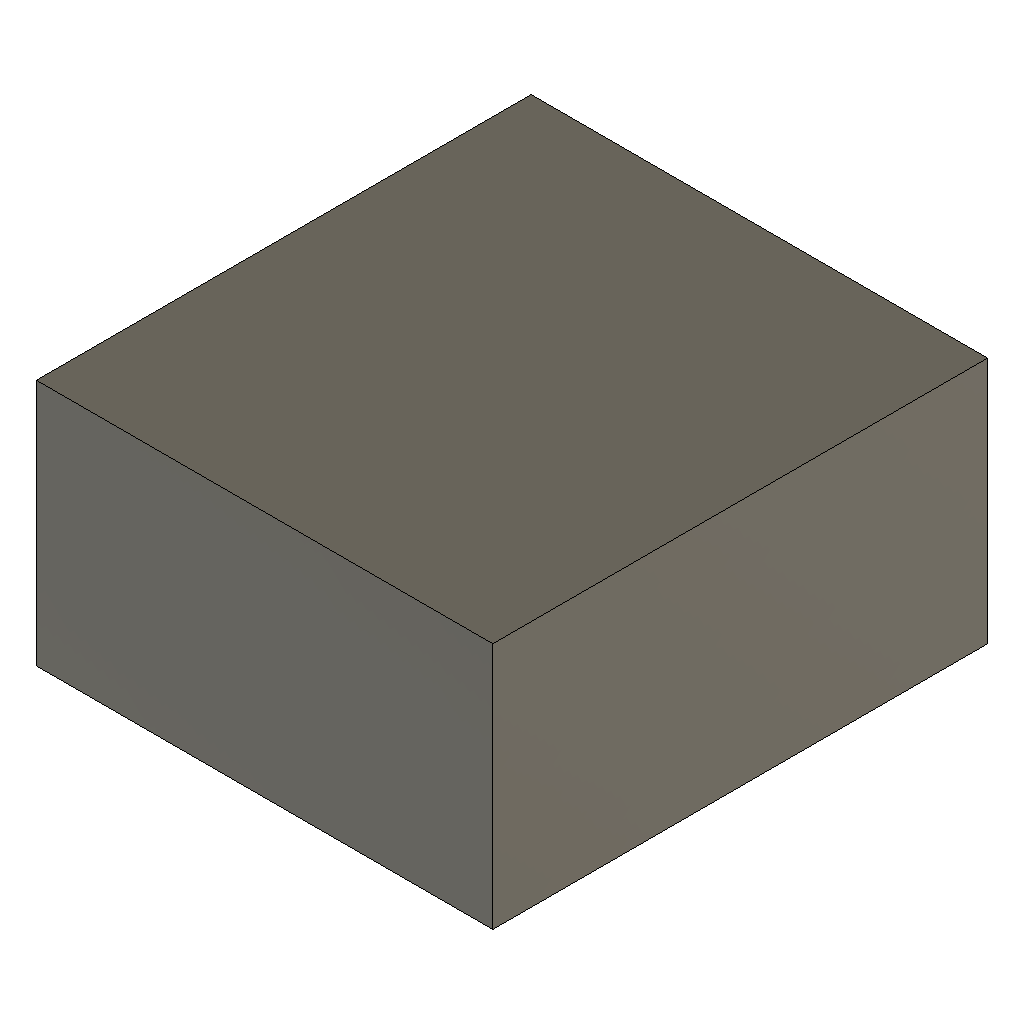
f2sc-test-split (Autodesk Fusion 360 design; units mm, degrees)
part number: 2026-11-27-15-42-43-917
Autodesk Fusion 360 part; units mm, degrees
sketch "Sketch1" plane through (0, 0, 0) normal (0, 0, 1) x (1, 0, 0)
  line L0 (-21.5502, -10.6882) -> (18.4498, -10.6882)
  line L1 (18.4498, -10.6882) -> (18.4498, 9.3118)
  line L2 (18.4498, 9.3118) -> (-21.5502, 9.3118)
  line L3 (-21.5502, 9.3118) -> (-21.5502, -10.6882)
  dimension "d1" = 40
  dimension "d2" = 20
  constraint horizontal L0
  constraint vertical L1
  constraint horizontal L2
  constraint vertical L3
  measures "d1" distance of L0.start L0.end
  measures "d2" distance of L0.start L2.end
extrude "Extrude1" add sketch "Sketch1" along normal blind 10 makes body 1
split "Split1" by plane through (0, 0, 0) normal (1, 0, 0) bodies 1 makes body 2 at (6.1499, -4.0215, 0)
delete_body "RemoveBody1" bodies 1
